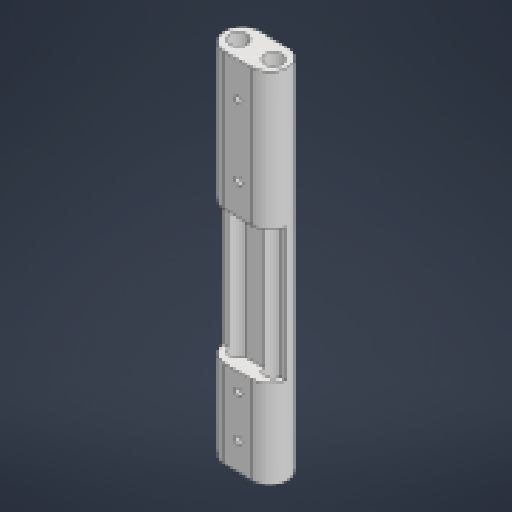
# Autodesk Inventor part: 现有铰链
Saved by Autodesk Inventor 2025 (Build 290162000, 162)
## iProperties
Created: 2025-10-09
Part Number: 现有铰链
Material: 常规
Document SubType Name: Modeling
Designer: HZD
Density: 1 g/cm^3
Appearance: 默认
Author: HZD
Autodesk Inventor part; units mm, degrees
ref_plane "YZ Plane" through (0, 0, 0) normal (1, 0, 0) x (0, 1, 0)
ref_plane "XZ Plane" through (0, 0, 0) normal (0, 1, 0) x (-1, 0, 0)
ref_plane "XY Plane" through (0, 0, 0) normal (0, 0, 1) x (1, 0, 0)
sketch "草图1" plane through (0, 0, 0) normal (0, 1, 0) x (-1, 0, 0)
  line L0 (-2, 0) -> (2, 0) construction
  line L1 (-2, 2.5) -> (2, 2.5)
  line L2 (2, -2.5) -> (-2, -2.5)
  arc A0 (-2, 2.5) -> (-2, -2.5) centre (-2, 0) ccw
  arc A1 (2, -2.5) -> (2, 2.5) centre (2, 0) ccw
  point P0 (0, 0)
  point P1 (-4.5, 0)
  point P2 (4.5, 0)
  dimension "d2" = 9
  dimension "d3" = 5
  constraints: 8 end point, 6 point on circle, 4 tangent, 2 centre point, 1 horizontal, 1 midpoint, 1 parallel
  measures "d2" distance of point (-4.5, 0) point (4.5, 0)
  measures "d3" distance between parallel lines of L1 L2
extrude "拉伸1" add sketch "草图1" along normal blind 51
sketch "草图2" plane through (-2, 0, 2.5) normal (0, 0, 1) x (1, 0, 0)
  line L0 (-2.5, 0) -> (6.5, 0)
  line L1 (6.5, 0) -> (6.5, 12)
  line L2 (6.5, 12) -> (-2.5, 12)
  line L3 (-2.5, 12) -> (-2.5, 0)
  line L4 (-2.5, 0) -> (-2.5, 51) projected
  line L5 (6.5, 0) -> (6.5, 51) projected
  line L6 (2, 12) -> (2, 0)
  circle A0 centre (2, 4) radius 0.5
  line L7 (6.5, 0) -> (4, 0) projected
  circle A1 centre (2, 10) radius 0.5
  dimension "d6" = 12
  dimension "d7" = 1
  dimension "d8" = 4
  dimension "d9" = 6
  dimension "d26" = 1
  constraints: 10 end point, 3 collinear, 2 centre point, 2 parallel, 2 point on line, 1 horizontal, 1 midpoint, 1 perpendicular, 1 vertical
  measures "d6" distance of L0.end L1.end
  measures "d7" diameter of A0
  measures "d8" distance from line of A0.centre L0
  measures "d9" distance of A0.centre A1.centre
  measures "d26" diameter of A1
extrude "拉伸2" cut sketch "草图2" against normal blind 51 contours A0 L6 | L6 A0 | A1 L6 | L6 A1
sketch "草图3" plane through (-2, 0, 2.5) normal (0, 0, 1) x (1, 0, 0)
  line L0 (-4.5026, 12.5) -> (14.1662, 12.5)
  line L1 (14.1662, 12.5) -> (14.1662, 31.5)
  line L2 (14.1662, 31.5) -> (-4.5026, 31.5)
  line L3 (-4.5026, 31.5) -> (-4.5026, 12.5)
  line L4 (6.5, 0) -> (4, 0) projected
  point P0 (2, 0)
  dimension "d12" = 12.5
  dimension "d13" = 19
  constraints: 8 end point, 2 parallel, 1 horizontal, 1 perpendicular
  measures "d12" distance between parallel lines of L0 L4
  measures "d13" distance of L0.end L1.end
extrude "拉伸3" cut sketch "草图3" against normal blind 2.25
sketch "草图4" plane through (0, 0, 0) normal (0, -1, 0) x (1, 0, 0)
  arc A0 (-2, 2.5) -> (-2, -2.5) centre (-2, 0) ccw projected
  line L0 (-4.5, 0) -> (4.5, 0)
  arc A1 (2, -2.5) -> (2, 2.5) centre (2, 0) ccw projected
  circle A2 centre (-2.5, 0) radius 1.25
  line L1 (-0.5, 2.5) -> (0.5, 2.5) projected
  line L2 (0, 2.5) -> (0, -2.5)
  line L3 (0.5, -2.5) -> (-0.5, -2.5) projected
  circle A3 centre (2.5, 0) radius 1.25
  point P0 (0, 0)
  point P1 (-4.5, 0)
  dimension "d16" = 2
  dimension "d17" = 2.5
  constraints: 4 end point, 3 point on circle, 2 centre point, 2 midpoint, 1 horizontal, 1 point on line, 1 symmetric about line, 1 other
  measures "d16" distance of point (-4.5, 0) A2.centre
  measures "d17" diameter of A2
extrude "拉伸4" cut sketch "草图4" against normal blind 71.5
sketch "草图5" plane through (-2, 51, 2.5) normal (0, 0, 1) x (1, 0, 0)
  line L0 (2, -51) -> (2, 0)
  circle A0 centre (2, -5) radius 0.5
  circle A1 centre (2, -15) radius 0.5
  line L1 (0, 0) -> (4, 0) projected
  dimension "d20" = 1
  dimension "d21" = 1
  dimension "d22" = 10
  dimension "d23" = 5
  constraints: 2 centre point, 2 end point, 2 point on line, 1 midpoint, 1 vertical
  measures "d20" diameter of A1
  measures "d21" diameter of A0
  measures "d22" distance of A1.centre A0.centre
  measures "d23" distance from line of L1 A0.centre
extrude "拉伸5" cut sketch "草图5" against normal blind 71.5
